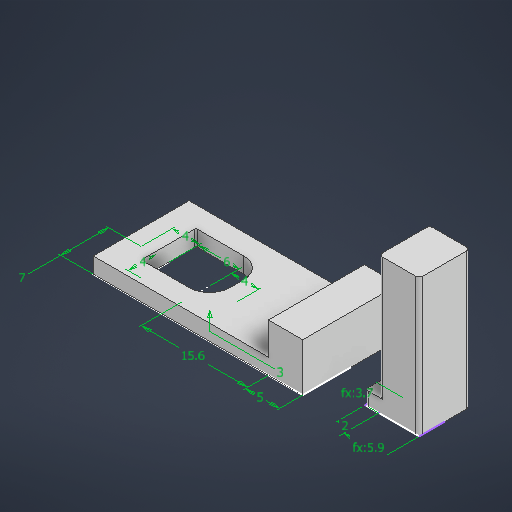
# Autodesk Inventor part: sujeccion_inferior
Saved by Autodesk Inventor 2027 (Build 310192060, 192F)
## iProperties
Created: 2026-10-17
Part Number: sujeccion_inferior
Material: Generic
Document SubType Name: Modeling
Designer: Pablo
Density: 1 g/cm^3
Appearance: Default
Author: Pablo
Autodesk Inventor part; units mm, degrees
ref_plane "YZ Plane" through (0, 0, 0) normal (1, 0, 0) x (0, 1, 0)
ref_plane "XZ Plane" through (0, 0, 0) normal (0, 1, 0) x (-1, 0, 0)
ref_plane "XY Plane" through (0, 0, 0) normal (0, 0, 1) x (1, 0, 0)
sketch "Sketch1" plane through (0, 0, 0) normal (0, 1, 0) x (-1, 0, 0)
  line L0 (0, 0) -> (0, 7)
  line L1 (0, 7) -> (30.6, 7)
  line L2 (30.6, 7) -> (30.6, 0)
  line L3 (30.6, 0) -> (26.6, 0)
  line L4 (26.6, 0) -> (26.6, 4)
  line L5 (26.6, 4) -> (19.6, 4)
  line L6 (16.6, 1) -> (16.6, 0)
  line L7 (16.6, 0) -> (0, 0)
  line L8 (5, 0) -> (5, 7)
  line L9 (20.6, 4) -> (20.6, 0) construction
  arc A0 (19.6, 4) -> (16.6, 1) centre (19.6, 1) ccw
  line L10 (-7.8329, 0) -> (-13.7329, 0)
  line L11 (-13.7329, 0) -> (-13.7329, 3.7)
  line L12 (-13.7329, 3.7) -> (-7.8329, 3.7)
  line L13 (-7.8329, 3.7) -> (-7.8329, 0)
  line L14 (-7.8329, 3.7) -> (-5.8329, 3.7)
  line L15 (-5.8329, 3.7) -> (-5.8329, 0)
  line L16 (-5.8329, 0) -> (-7.8329, 0)
  dimension "d0" = 5
  dimension "d1" = 7
  dimension "d2" = 4
  dimension "d3" = 4
  dimension "d6" = 6
  dimension "d7" = 15.6
  dimension "d8" = 4
  dimension "d9" = 3
  dimension "d10" = 3.7
  dimension "d11" = 5.9
  dimension "d16" = 2
  constraints: 34 end point, 12 perpendicular, 4 point on line, 2 horizontal, 2 parallel, 2 point on circle, 2 tangent, 1 centre point, 1 collinear, 1 vertical
  measures "d0" distance between parallel lines of L0 L8
  measures "d1" distance between parallel lines of L3 L1
  measures "d2" distance between parallel lines of L3 L5
  measures "d3" distance between parallel lines of L4 L2
  measures "d6" distance between parallel lines of L9 L4
  measures "d7" distance between parallel lines of L8 L9
  measures "d8" distance between parallel lines of L9 L6
  measures "d9" radius of A0
  measures "d10" distance of L12.end L10.start
  measures "d11" distance of L11.end L12.end
  measures "d16" distance of L12.end L14.end
extrude "Extrusion1" add sketch "Sketch1" along normal blind 2.3 contours L8 L1 L2 L3 L4 L5 A0 L6 L7
extrude "Extrusion2" add sketch "Sketch1" along normal blind 7 contours L0 L1 L8 L7
extrude "Extrusion3" add sketch "Sketch1" along normal blind 2 contours L13 L14 L15 L16
extrude "Extrusion4" add sketch "Sketch1" along normal blind 20 contours L10 L11 L12 L13
mirror "Mirror1" about plane through (7.8329, 0, 0) normal (0, 0, -1)
fillet "Fillet1" radius 0.5 6 edges at (5.8329, 1, 3.7) (7.8329, 11, 3.7) (5.8329, 1, -3.7) (7.8329, 11, -3.7) (13.7329, 10, 3.7) (13.7329, 10, -3.7)
fillet "Fillet2" radius 0.2 2 edges at (-26.6, 1.15, 4) (-26.6, 1.15, -4)
body "Solid1"
